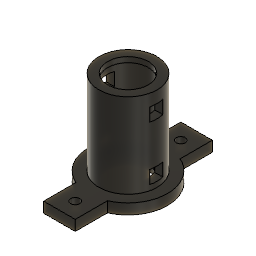
03_brush_cartridge_editable (Autodesk Fusion 360 design; units mm, degrees)
part number: 2026-10-21-18-29-23-563
Autodesk Fusion 360 part; units mm, degrees
ref_plane "作業平面1" through (0, 0, 8.5) normal (0, 0, 1) x (1, 0, 0)
sketch "スケッチ1" plane through (0, 0, 8.5) normal (0, 0, 1) x (1, 0, 0)
  circle A0 centre (50, 2.7629) radius 15
  dimension "d704" = 30
  measures "d704" diameter of A0
extrude "Flat_printing_flange" add sketch "スケッチ1" along normal blind 4
ref_plane "作業平面2" through (0, 0, 8.5) normal (0, 0, 1) x (1, 0, 0)
sketch "スケッチ2" plane through (0, 0, 8.5) normal (0, 0, 1) x (1, 0, 0)
  line L0 (44, -23.2371) -> (56, -23.2371)
  line L1 (56, -23.2371) -> (56, -10.2371)
  line L2 (56, -10.2371) -> (44, -10.2371)
  line L3 (44, -10.2371) -> (44, -23.2371)
extrude "Cartridge_ear_-1" add sketch "スケッチ2" along normal blind 4
ref_plane "作業平面3" through (0, 0, 8.5) normal (0, 0, 1) x (1, 0, 0)
sketch "スケッチ3" plane through (0, 0, 8.5) normal (0, 0, 1) x (1, 0, 0)
  line L0 (44, 15.7629) -> (56, 15.7629)
  line L1 (56, 15.7629) -> (56, 28.7629)
  line L2 (56, 28.7629) -> (44, 28.7629)
  line L3 (44, 28.7629) -> (44, 15.7629)
extrude "Cartridge_ear_1" add sketch "スケッチ3" along normal blind 4
ref_plane "作業平面4" through (0, 0, 8.5) normal (0, 0, 1) x (1, 0, 0)
sketch "スケッチ4" plane through (0, 0, 8.5) normal (0, 0, 1) x (1, 0, 0)
  circle A0 centre (50, 2.7629) radius 11
  dimension "d717" = 22
  measures "d717" diameter of A0
extrude "Cartridge_vertical_sleeve" add sketch "スケッチ4" along normal blind 36
ref_plane "作業平面5" through (0, 0, 8.5) normal (0, 0, 1) x (1, 0, 0)
sketch "スケッチ5" plane through (0, 0, 8.5) normal (0, 0, 1) x (1, 0, 0)
  circle A0 centre (50, 2.7629) radius 8
  dimension "d722" = 16
  measures "d722" diameter of A0
extrude "Cartridge_parameterized_bore" cut sketch "スケッチ5" along normal blind 36
ref_plane "作業平面6" through (0, 0, 8.5) normal (0, 0, 1) x (1, 0, 0)
sketch "スケッチ6" plane through (0, 0, 8.5) normal (0, 0, 1) x (1, 0, 0)
  circle A0 centre (50, -17.2371) radius 1.7
  circle A1 centre (50, 22.7629) radius 1.7
  dimension "d727" = 3.4
  dimension "d728" = 3.4
  measures "d727" diameter of A0
  measures "d728" diameter of A1
extrude "Cartridge_M3_clearance" cut sketch "スケッチ6" along normal blind 4
ref_plane "作業平面7" through (0, 0, 8.5) normal (0, 0, 1) x (1, 0, 0)
sketch "スケッチ7" plane through (0, 0, 8.5) normal (0, 0, 1) x (1, 0, 0)
  circle A0 centre (50, 2.7629) radius 11
  dimension "d733" = 22
  measures "d733" diameter of A0
extrude "Brush_centering_land" add sketch "スケッチ7" along normal blind 2
ref_plane "作業平面8" through (0, 0, 8.5) normal (0, 0, 1) x (1, 0, 0)
sketch "スケッチ8" plane through (0, 0, 8.5) normal (0, 0, 1) x (1, 0, 0)
  circle A0 centre (50, 2.7629) radius 7.7
  dimension "d738" = 15.4
  measures "d738" diameter of A0
extrude "Brush_non_clamping_centering_guide" cut sketch "スケッチ8" along normal blind 2
ref_plane "作業平面9" through (0, 0, 42.5) normal (0, 0, 1) x (1, 0, 0)
sketch "スケッチ9" plane through (0, 0, 42.5) normal (0, 0, 1) x (1, 0, 0)
  circle A0 centre (50, 2.7629) radius 11
  dimension "d743" = 22
  measures "d743" diameter of A0
extrude "Brush_centering_land (1)" add sketch "スケッチ9" along normal blind 2
ref_plane "作業平面10" through (0, 0, 42.5) normal (0, 0, 1) x (1, 0, 0)
sketch "スケッチ10" plane through (0, 0, 42.5) normal (0, 0, 1) x (1, 0, 0)
  circle A0 centre (50, 2.7629) radius 7.7
  dimension "d748" = 15.4
  measures "d748" diameter of A0
extrude "Brush_non_clamping_centering_guide (1)" cut sketch "スケッチ10" along normal blind 2
ref_plane "作業平面11" through (37, 0, 0) normal (1, 0, 0) x (0, 1, 0)
sketch "スケッチ11" plane through (37, 0, 0) normal (1, 0, 0) x (0, 0, -1)
  line L0 (-14.5, 0.2629) -> (-14.5, 5.2629)
  line L1 (-14.5, 5.2629) -> (-19.5, 5.2629)
  line L2 (-19.5, 5.2629) -> (-19.5, 0.2629)
  line L3 (-19.5, 0.2629) -> (-14.5, 0.2629)
extrude "Hot_glue_through_keys_14.5" cut sketch "スケッチ11" along normal blind 26
ref_plane "作業平面12" through (37, 0, 0) normal (1, 0, 0) x (0, 1, 0)
sketch "スケッチ12" plane through (37, 0, 0) normal (1, 0, 0) x (0, 0, -1)
  line L0 (-35, 0.2629) -> (-35, 5.2629)
  line L1 (-35, 5.2629) -> (-40, 5.2629)
  line L2 (-40, 5.2629) -> (-40, 0.2629)
  line L3 (-40, 0.2629) -> (-35, 0.2629)
extrude "Hot_glue_through_keys_35" cut sketch "スケッチ12" along normal blind 26
equation "d704 = brush_flange_od"
equation "d705 = brush_flange_thickness"
equation "d709 = brush_flange_thickness"
equation "d713 = brush_flange_thickness"
equation "d717 = brush_cartridge_od"
equation "d718 = brush_sleeve_length"
equation "d722 = brush_cartridge_id"
equation "d723 = brush_sleeve_length"
equation "d727 = sc_screw_clearance"
equation "d728 = sc_screw_clearance"
equation "d729 = brush_flange_thickness"
equation "d733 = brush_cartridge_od"
equation "d738 = brush_guide_dia"
equation "d743 = brush_cartridge_od"
equation "d748 = brush_guide_dia"
equation "brush_dia = 15 mm" comment "ç­è»¸ã®ç´å¾ â å®æ¸¬"
equation "sc_screw_clearance = 3.4 mm" comment "Printed base M3 clearance; sensor itself has M3 threaded holes"
equation "brush_glue_allowance = 1.0 mm" comment "Diametral allowance for hot glue around brush"
equation "brush_cartridge_od = 22 mm" comment "Rigid sleeve outside diameter; nominal wall 3 mm"
equation "brush_cartridge_id = brush_dia + brush_glue_allowance" comment "Nominal brush bore"
equation "brush_flange_od = brush_cartridge_od + 8 mm" comment "Cartridge load-bearing flange diameter"
equation "brush_sleeve_length = 36 mm" comment "Length of replaceable glued brush sleeve"
equation "brush_flange_thickness = 4 mm" comment "Cartridge flange thickness"
equation "brush_guide_dia = brush_dia + 0.4 mm" comment "Slip guide at both sleeve ends; no clamp or interference fit"
named bodies: "Brush_Cartridge_15mm_FDM"
